Autodesk Fusion 360 part; units mm, degrees
(part 2 of 3)
sketch "Sketch4" plane through (0, 0, 0) normal (0, 0, 1) x (-1, 0, 0)
  line L0 (0, -15.875) -> (0, -11.049)
  line L1 (0, -11.049) -> (-10.16, -11.049)
  line L2 (-10.16, -11.049) -> (-10.16, -15.875)
  line L3 (-10.16, -15.875) -> (0, -15.875)
sketch "Sketch5" plane through (10.16, 0, 0) normal (1, 0, 0) x (0, -1, 0)
  line L0 (-11.049, 0.762) -> (-0.762, 11.049)
  line L1 (-0.762, 11.049) -> (0.762, 11.049)
  line L2 (0.762, 11.049) -> (11.049, 0.762)
  line L3 (11.049, 0.762) -> (11.049, 0)
  line L4 (11.049, 0) -> (15.875, 0)
  line L5 (15.875, 0) -> (15.875, 12.7)
  line L6 (15.875, 12.7) -> (-15.875, 12.7)
  line L7 (-15.875, 12.7) -> (-15.875, 0)
  line L8 (-15.875, 0) -> (-11.049, 0)
  line L9 (-11.049, 0) -> (-11.049, 0.762)
  arc A0 (-12.7, 0) -> (12.7, 0) centre (0, 0) ccw
  line L10 (-11.6397, -5.08) -> (15.875, -5.08)
  line L11 (11.6397, -5.08) -> (-15.875, -5.08)
  line L12 (-15.875, 0) -> (-11.049, 0)
  dimension "d21" = 5.08
  dimension "d22" = 5.08
  dimension "d34" = 12.7
  constraint coincident A0.centre origin
  constraint coincident L8 A0.end
  constraint coincident L4 A0.start
  constraint coincident A0 L10.start
  constraint coincident L5 L10.end
  constraint perpendicular L5 L10
  constraint coincident A0 L11.start
  constraint coincident L7 L11.end
  constraint perpendicular L7 L11
  measures "d21" distance of L4 L10
  measures "d22" distance of L11 L12
  measures "d34" radius of A0
extrude "Extrude3" add sketch "Sketch5" against normal up to surface (10.16 mm away) contours L0 L1 L2 L3 L4 L5 L6 L7 L8 L9 L12
sketch "Sketch7" plane through (0, 0, 0) normal (0, 0, 1) x (-1, 0, 0)
  line L0 (0, 11.049) -> (0, 15.875)
  line L1 (0, 15.875) -> (-10.16, 15.875)
  line L2 (-10.16, 15.875) -> (-10.16, 11.049)
  line L3 (-10.16, 11.049) -> (0, 11.049)
  circle A0 centre (-5.08, 13.589) radius 1.6
  circle A1 centre (-5.08, -13.589) radius 1.6
  line L4 (-10.16, -15.875) -> (0, -15.875)
  line L5 (-10.16, -11.049) -> (-10.16, -15.875)
  dimension "d35" = 3.2
  dimension "d36" = 3.2
  dimension "d37" = 2.286
  dimension "d38" = 2.286
  dimension "d39" = 5.08
  dimension "d40" = 5.08
  measures "d35" diameter of A1
  measures "d36" diameter of A0
  measures "d37" distance of A1.centre L4
  measures "d38" distance of L1 A0.centre
  measures "d39" distance of L2 A0.centre
  measures "d40" distance of A1.centre L5
extrude "Extrude5" cut sketch "Sketch7" against normal blind 12.7 contours A0 | A1
sketch "Sketch8" plane through (0, 0, 0) normal (-1, 0, 0) x (0, -1, 0)
  line L0 (-0.762, -11.049) -> (-11.049, -0.762)
  line L1 (-11.049, -0.762) -> (-11.049, 0)
  line L2 (-11.049, 0) -> (-15.875, 0)
  line L3 (-15.875, 0) -> (-15.875, -12.7)
  line L4 (-15.875, -12.7) -> (15.875, -12.7)
  line L5 (15.875, -12.7) -> (15.875, 0)
  line L6 (15.875, 0) -> (11.049, 0)
  line L7 (11.049, 0) -> (11.049, -0.762)
  line L8 (11.049, -0.762) -> (0.762, -11.049)
  line L9 (0.762, -11.049) -> (-0.762, -11.049)
  arc A0 (-12.7, 0) -> (12.7, 0) centre (0, 0) ccw
  line L10 (-11.6397, -5.08) -> (-15.875, -5.08)
  line L11 (11.6397, -5.08) -> (15.875, -5.08)
  line L12 (-15.875, 0) -> (-11.049, 0)
  dimension "d43" = 5.08
  dimension "d44" = 5.08
  constraint coincident A0.centre origin
  constraint tangent L4 A0
  constraint coincident L6 A0.end
  constraint coincident L2 A0.start
  constraint coincident A0 L10.start
  constraint coincident L3 L10.end
  constraint perpendicular L3 L10
  constraint coincident A0 L11.start
  constraint coincident L5 L11.end
  constraint perpendicular L5 L11
  measures "d43" distance of L10 L12
  measures "d44" distance of L6 L11
extrude "Extrude6" cut sketch "Sketch8" against normal blind 10.16 contours L3 L4 A0 L10 | L4 L5 A0 L11

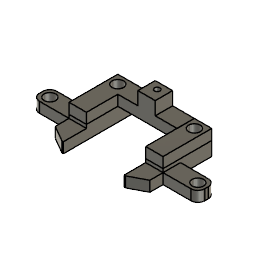
design "Static Arm"
Autodesk Fusion 360 part; units mm, degrees
sketch "Sketch1" plane through (0, 0, 0) normal (0, 0, 1) x (1, 0, 0)
  line L0 (2.54, 0) -> (57.7596, 0)
  line L1 (60.2996, 2.54) -> (60.2996, 3.81)
  line L2 (57.7596, 6.35) -> (2.54, 6.35)
  line L3 (0, 3.81) -> (0, 2.54)
  circle A0 centre (3.175, 3.175) radius 2.0955
  circle A1 centre (57.1246, 3.175) radius 2.0955
  arc A2 (60.2996, 3.81) -> (57.7596, 6.35) centre (57.7596, 3.81) ccw
  arc A3 (57.7596, 0) -> (60.2996, 2.54) centre (57.7596, 2.54) ccw
  arc A4 (2.54, 6.35) -> (0, 3.81) centre (2.54, 3.81) ccw
  arc A5 (0, 2.54) -> (2.54, 0) centre (2.54, 2.54) ccw
  line L4 (13.335, 17.78) -> (41.275, 17.78)
  line L5 (41.275, 17.78) -> (41.275, 11.43)
  line L6 (41.275, 11.43) -> (13.335, 11.43)
  line L7 (13.335, 11.43) -> (13.335, 17.78)
  line L8 (13.335, 17.78) -> (19.685, 17.78)
  line L9 (19.685, 17.78) -> (19.685, 0)
  line L10 (19.685, 0) -> (13.335, 0)
  line L11 (13.335, 0) -> (13.335, 17.78)
  line L12 (47.5996, 17.78) -> (41.2496, 17.78)
  line L13 (41.2496, 17.78) -> (41.2496, 0)
  line L14 (41.2496, 0) -> (47.5996, 0)
  line L15 (47.5996, 0) -> (47.5996, 17.78)
  point P0 (60.2996, 0)
  dimension "d1" = 6.35
  dimension "d2" = 60.2996
  dimension "d3" = 4.191
  dimension "d4" = 4.191
  dimension "d5" = 53.9496
  dimension "d6" = 3.175
  dimension "d7" = 3.175
  dimension "d8" = 2.54
  dimension "d9" = 2.54
  dimension "d10" = 2.54
  dimension "d11" = 2.54
  dimension "d14" = 6.35
  dimension "d15" = 10.16
  dimension "d17" = 6.35
  dimension "d18" = 10.16
  dimension "d19" = 5.08
  dimension "d20" = 6.35
  dimension "d39" = 27.94
  constraint horizontal L0
  constraint vertical L1
  constraint horizontal L2
  constraint vertical L3
  constraint horizontal A0.centre A1.centre
  constraint tangent L2 A2
  constraint tangent L1 A2
  constraint coincident P0 L0
  constraint coincident P0 L1
  constraint tangent L0 A3
  constraint tangent L1 A3
  constraint tangent L3 A4
  constraint tangent L2 A4
  constraint coincident origin L3
  constraint coincident origin L0
  constraint tangent L3 A5
  constraint tangent L0 A5
  constraint horizontal L4
  constraint vertical L5
  constraint horizontal L6
  constraint vertical L7
  constraint horizontal L8
  constraint vertical L9
  constraint horizontal L10
  constraint vertical L11
  constraint coincident L0 L9.end
  constraint horizontal L12
  constraint vertical L13
  constraint horizontal L14
  constraint vertical L15
  constraint coincident L0 L13.end
  constraint coincident L4 L12.start
  measures "d1" distance of L0 L2
  measures "d2" distance of origin P0
  measures "d3" diameter of A0
  measures "d4" diameter of A1
  measures "d5" distance of A0.centre A1.centre
  measures "d6" distance of L3 A0.centre
  measures "d7" vertical distance of origin A0.centre
  measures "d8" radius of A2
  measures "d9" radius of A3
  measures "d10" radius of A4
  measures "d11" radius of A5
  measures "d14" distance of L4 L6
  measures "d15" distance of A0.centre L11
  measures "d17" distance of L13 L15
  measures "d18" distance of A3.centre L15
  measures "d19" distance of L2 L6
  measures "d20" distance of L9 L11
  measures "d39" distance of L4.start L4.end
extrude "Extrude1" add sketch "Sketch1" along normal blind 3.81 contours L0 L2 L3 A4 A5 L11 | L0 L2 L9 L10 L11 | L2 L6 L9 L11 | L0 L2 L13 L14 L15 | L4 L6 L7 L8 L9 L11 | L0 L1 L2 A2 A3 L15 | L2 L5 L6 L12 L13 L15 | L4 L6 L9 L13 makes body 1
sketch "Sketch5" plane through (0, 0, 3.81) normal (0, 0, -1) x (1, 0, 0)
  circle A0 centre (63.4746, -3.175) radius 2.0955
  circle A1 centre (3.175, -3.175) radius 2.0955
  line L0 (47.5996, 0) -> (47.5996, -11.43)
  line L1 (47.5996, -11.43) -> (19.335, -11.43)
  line L2 (19.335, -11.43) -> (19.335, 0)
  line L3 (19.335, 0) -> (2.54, 0)
  arc A2 (2.54, 0) -> (0, -2.54) centre (2.54, -2.54) ccw
  line L4 (0, -2.54) -> (0, -3.81)
  arc A3 (0, -3.81) -> (2.54, -6.35) centre (2.54, -3.81) ccw
  line L5 (2.54, -6.35) -> (13.335, -6.35)
  line L6 (13.335, -6.35) -> (13.335, -17.78)
  line L7 (13.335, -17.78) -> (53.9496, -17.78)
  line L8 (53.9496, -17.78) -> (53.9496, -6.35)
  line L9 (53.9496, -6.35) -> (64.1096, -6.35)
  arc A4 (64.1096, -6.35) -> (66.6496, -3.81) centre (64.1096, -3.81) ccw
  line L10 (66.6496, -3.81) -> (66.6496, -2.54)
  arc A5 (66.6496, -2.54) -> (64.1096, 0) centre (64.1096, -2.54) ccw
  line L11 (64.1096, 0) -> (47.5996, 0)
  line L12 (26.9748, -11.43) -> (33.3248, -11.43)
  line L13 (33.3248, -11.43) -> (33.3248, -17.78)
  line L14 (33.3248, -17.78) -> (26.9748, -17.78)
  line L15 (26.9748, -17.78) -> (26.9748, -11.43)
  circle A6 centre (3.175, -3.175) radius 2.0955
  line L16 (13.335, -17.78) -> (13.335, -6.35)
  line L17 (13.335, -6.35) -> (2.54, -6.35)
  arc A7 (0, -3.81) -> (2.54, -6.35) centre (2.54, -3.81) ccw
  line L18 (0, -3.81) -> (0, -2.54)
  arc A8 (2.54, 0) -> (0, -2.54) centre (2.54, -2.54) ccw
  line L19 (2.54, 0) -> (19.685, 0)
  line L20 (19.685, 0) -> (19.685, -11.43)
  line L21 (19.685, -11.43) -> (41.2496, -11.43)
  line L22 (41.2496, -11.43) -> (41.2496, -17.78)
  line L23 (41.2496, -17.78) -> (13.335, -17.78)
  dimension "d35" = 6.35
  dimension "d36" = 26.9748
  constraint horizontal L12
  constraint vertical L13
  constraint horizontal L14
  constraint vertical L15
  constraint coincident L7 L13.end
  constraint coincident L1 L12.start
  measures "d35" distance of L13 L15
  measures "d36" distance of origin L15
extrude "Extrude4" add sketch "Sketch5" against normal blind 4.8006 contours L1 L7 L12 L13 L14 L15 L21 L23 bodies 1
sketch "Sketch2" plane through (0, 0, 8.6106) normal (0, 0, -1) x (1, 0, 0)
  circle A0 centre (63.4746, -3.175) radius 2.0955
  circle A1 centre (3.175, -3.175) radius 2.0955
  line L0 (47.5996, 0) -> (47.5996, -11.43)
  line L1 (47.5996, -11.43) -> (36.4998, -11.43)
  line L2 (19.335, -11.43) -> (19.335, 0)
  line L3 (19.335, 0) -> (2.54, 0)
  arc A2 (2.54, 0) -> (0, -2.54) centre (2.54, -2.54) ccw
  line L4 (0, -2.54) -> (0, -3.81)
  arc A3 (0, -3.81) -> (2.54, -6.35) centre (2.54, -3.81) ccw
  line L5 (2.54, -6.35) -> (13.335, -6.35)
  line L6 (13.335, -6.35) -> (13.335, -17.78)
  line L7 (36.4998, -17.78) -> (53.9496, -17.78)
  line L8 (53.9496, -17.78) -> (53.9496, -6.35)
  line L9 (53.9496, -6.35) -> (64.1096, -6.35)
  arc A4 (64.1096, -6.35) -> (66.6496, -3.81) centre (64.1096, -3.81) ccw
  line L10 (66.6496, -3.81) -> (66.6496, -2.54)
  arc A5 (66.6496, -2.54) -> (64.1096, 0) centre (64.1096, -2.54) ccw
  line L11 (64.1096, 0) -> (47.5996, 0)
  circle A6 centre (30.1498, -15.3416) radius 1
  line L12 (36.4998, -11.43) -> (36.4998, -17.78)
  line L13 (30.1498, -17.78) -> (30.1498, -11.43)
  line L14 (30.1498, -11.43) -> (19.335, -11.43)
  line L15 (13.335, -17.78) -> (30.1498, -17.78)
  line L16 (30.1498, -17.78) -> (36.4998, -17.78)
  line L17 (36.4998, -17.78) -> (36.4998, -11.43)
  line L18 (36.4998, -11.43) -> (30.1498, -11.43)
  line L19 (30.1498, -11.43) -> (30.1498, -17.78)
  circle A7 centre (63.4746, -3.175) radius 2.0955
  circle A8 centre (3.175, -3.175) radius 2.0955
  line L20 (47.5996, -11.43) -> (47.5996, 0)
  line L21 (2.54, 0) -> (19.335, 0)
  arc A9 (66.6496, -2.54) -> (64.1096, 0) centre (64.1096, -2.54) ccw
  line L22 (66.6496, -2.54) -> (66.6496, -3.81)
  arc A10 (64.1096, -6.35) -> (66.6496, -3.81) centre (64.1096, -3.81) ccw
  line L23 (13.335, -6.35) -> (2.54, -6.35)
  line L24 (53.9496, -6.35) -> (53.9496, -17.78)
  line L25 (30.1498, -17.78) -> (13.335, -17.78)
  line L26 (13.335, -17.78) -> (13.335, -6.35)
  arc A11 (0, -3.81) -> (2.54, -6.35) centre (2.54, -3.81) ccw
  line L27 (0, -3.81) -> (0, -2.54)
  arc A12 (2.54, 0) -> (0, -2.54) centre (2.54, -2.54) ccw
  line L28 (19.335, 0) -> (19.335, -11.43)
  line L29 (19.335, -11.43) -> (30.1498, -11.43)
  line L30 (30.1498, -11.43) -> (30.1498, -17.78)
  line L31 (36.4998, -17.78) -> (36.4998, -11.43)
  line L32 (36.4998, -11.43) -> (47.5996, -11.43)
  line L33 (47.5996, 0) -> (64.1096, 0)
  line L34 (64.1096, -6.35) -> (53.9496, -6.35)
  line L35 (53.9496, -17.78) -> (36.4998, -17.78)
  line L36 (33.3248, -17.78) -> (26.9748, -17.78)
  line L37 (26.9748, -17.78) -> (26.9748, -11.43)
  line L38 (26.9748, -11.43) -> (33.3248, -11.43)
  line L39 (33.3248, -11.43) -> (33.3248, -17.78)
  dimension "d21" = 2
  dimension "d24" = 3.9116
  dimension "d53" = 30.1498
  measures "d21" diameter of A6
  measures "d24" distance of L1 A6.centre
  measures "d53" distance of L4 A6.centre
extrude "Extrude2" cut sketch "Sketch2" along normal blind 12.7 contours A6 L13 L19 L30 | A6 L13 L19 L30 bodies 1
sketch "Sketch3" plane through (0, 0, 3.81) normal (0, 0, 1) x (-1, 0, 0)
  line L0 (-41.2496, 0) -> (-57.7596, 0)
  line L1 (-57.7596, -6.35) -> (-47.5996, -6.35)
  line L2 (-41.275, -11.43) -> (-41.2496, -11.43)
  circle A0 centre (-16.51, -14.605) radius 2.1
  circle A1 centre (-44.4246, -14.605) radius 2.1
  line L3 (-47.5996, -6.35) -> (-47.5996, -17.78)
  line L4 (-47.5996, -17.78) -> (-41.275, -17.78)
  line L5 (-41.275, -17.78) -> (-41.275, -11.43)
  line L6 (-41.2496, -11.43) -> (-41.2496, 0)
  arc A2 (-57.7596, 0) -> (-60.2996, -2.54) centre (-57.7596, -2.54) ccw
  line L7 (-60.2996, -2.54) -> (-60.2996, -3.81)
  arc A3 (-60.2996, -3.81) -> (-57.7596, -6.35) centre (-57.7596, -3.81) ccw
  circle A4 centre (-57.1246, -3.175) radius 2.0955
  dimension "d27" = 4.2
  dimension "d28" = 4.2
  dimension "d40" = 14.605
  dimension "d41" = 16.51
  dimension "d42" = 27.9146
  constraint horizontal A0.centre A1.centre
  measures "d27" diameter of A1
  measures "d28" diameter of A0
  measures "d40" vertical distance of origin A0.centre
  measures "d41" horizontal distance of origin A0.centre
  measures "d42" distance of A0.centre A1.centre
extrude "Extrude3" cut sketch "Sketch3" against normal blind 3.81 contours A0 | A1 bodies 1
sketch "Sketch6" plane through (0, 0, 0) normal (0, 0, -1) x (1, 0, 0)
  circle A0 centre (44.4246, -14.605) radius 2.1
  circle A1 centre (57.1246, -3.175) radius 2.0955
  line L0 (47.5996, -6.35) -> (57.7596, -6.35)
  arc A2 (57.7596, -6.35) -> (60.2996, -3.81) centre (57.7596, -3.81) ccw
  line L1 (60.2996, -3.81) -> (60.2996, -2.54)
  arc A3 (60.2996, -2.54) -> (57.7596, 0) centre (57.7596, -2.54) ccw
  line L2 (57.7596, 0) -> (41.2496, 0)
  line L3 (41.2496, 0) -> (41.2496, -11.43)
  line L4 (41.2496, -11.43) -> (41.275, -11.43)
  line L5 (41.275, -11.43) -> (41.275, -17.78)
  line L6 (41.275, -17.78) -> (47.5996, -17.78)
  line L7 (47.5996, -17.78) -> (47.5996, -6.35)
  line L8 (41.2496, 0) -> (47.5996, 0)
  line L9 (47.5996, 0) -> (47.5996, -17.78)
  line L10 (47.5996, -17.78) -> (41.2496, -17.78)
  line L11 (41.2496, -17.78) -> (41.2496, 0)
  line L12 (47.5996, 0) -> (57.7596, 0)
  line L13 (60.2996, -2.54) -> (60.2996, -3.81)
  line L14 (57.7596, -6.35) -> (47.5996, -6.35)
  line L15 (47.5996, -6.35) -> (47.5996, 0)
  arc A4 (60.2996, -2.54) -> (57.7596, 0) centre (57.7596, -2.54) ccw
  arc A5 (57.7596, -6.35) -> (60.2996, -3.81) centre (57.7596, -3.81) ccw
  line L16 (19.685, -17.78) -> (13.335, -17.78)
  line L17 (13.335, -17.78) -> (13.335, 0)
  line L18 (13.335, 0) -> (19.685, 0)
  line L19 (19.685, 0) -> (19.685, -17.78)
  line L20 (13.335, 0) -> (2.54, 0)
  line L21 (0, -2.54) -> (0, -3.81)
  line L22 (2.54, -6.35) -> (13.335, -6.35)
  line L23 (13.335, -6.35) -> (13.335, 0)
  arc A6 (2.54, 0) -> (0, -2.54) centre (2.54, -2.54) ccw
  arc A7 (0, -3.81) -> (2.54, -6.35) centre (2.54, -3.81) ccw
  circle A8 centre (3.175, -3.175) radius 2.0955
  circle A9 centre (16.51, -14.5999) radius 2.0955
  point P0 (19.685, 0)
  point P1 (13.335, -17.78)
  point P2 (0, -2.54)
  dimension "d43" = 2.54
  dimension "d44" = 2.54
  dimension "d45" = 10.16
  dimension "d46" = 1.27
  dimension "d54" = 6.35
  dimension "d55" = 2.54
  dimension "d56" = 2.54
  dimension "d57" = 6.35
  dimension "d58" = 3.175
  dimension "d59" = 4.191
  dimension "d60" = 3.175
  dimension "d61" = 4.191
  dimension "d62" = 3.1801
  dimension "d63" = 3.175
  constraint horizontal L8
  constraint vertical L9
  constraint horizontal L10
  constraint vertical L11
  constraint coincident L6.end L7.start
  constraint coincident L2.end L3.start
  constraint horizontal L12
  constraint vertical L13
  constraint horizontal L14
  constraint vertical L15
  constraint tangent L12 A4
  constraint tangent L13 A4
  constraint tangent L13 A5
  constraint tangent L14 A5
  constraint horizontal L16
  constraint vertical L17
  constraint horizontal L18
  constraint vertical L19
  constraint coincident P0 L18.end
  constraint coincident P1 L16.end
  constraint horizontal L20
  constraint vertical L21
  constraint horizontal L22
  constraint vertical L23
  constraint tangent L21 A6
  constraint tangent L20 A6
  constraint tangent L21 A7
  constraint tangent L22 A7
  constraint coincident P2 L21.start
  measures "d43" radius of A4
  measures "d44" radius of A5
  measures "d45" distance of L0.start L0.end
  measures "d46" distance of L1.end A2.end
  measures "d54" distance of L17 L19
  measures "d55" radius of A6
  measures "d56" radius of A7
  measures "d57" distance of L20 L22
  measures "d58" distance of L20 A8.centre
  measures "d59" diameter of A8
  measures "d60" distance of L21 A8.centre
  measures "d61" diameter of A9
  measures "d62" distance of L16 A9.centre
  measures "d63" distance of L17 A9.centre
extrude "Extrude6" cut sketch "Sketch6" against normal blind 7.62 contours L0 A2 L1 A3 L2 L9 L12 L13 L14 L15 A4 A5 | L17 L20 L21 L22 L23 A6 A7 bodies 1
extrude "Extrude5" add sketch "Sketch6" along normal blind 5.08 separate body contours L0 A2 L1 A3 L2 L9 L12 L13 L14 L15 A4 A5 | L2 L3 L4 L5 L6 L7 L8 L9 L10 L11 L15 | L16 L17 L18 L19 L23 | L17 L20 L21 L22 L23 A6 A7 makes body 2 at (43.3747, 5.9267, 0) makes body 3 at (12.6943, 2.8719, 0)
extrude "Extrude7" cut sketch "Sketch6" along normal blind 1.27 contours L0 A2 L1 A3 L2 L9 L12 L13 L14 L15 A4 A5 | L17 L20 L21 L22 L23 A6 A7 bodies 2
extrude "Extrude8" cut sketch "Sketch6" along normal blind 1.27 contours L17 L20 L21 L22 L23 A6 A7 bodies 3
sketch "Sketch7" plane through (0, 0, 0) normal (0, -1, 0) x (1, 0, 0)
  line L0 (13.335, -1.27) -> (2.54, -1.27)
  line L1 (2.54, -1.27) -> (2.54, -5.08)
  line L2 (2.54, -5.08) -> (19.685, -5.08)
  line L3 (19.685, -5.08) -> (19.685, 0)
  line L4 (19.685, 0) -> (13.335, 0)
  line L5 (13.335, 0) -> (13.335, -1.27)
  line L6 (13.335, -1.27) -> (19.685, -1.27)
  line L7 (19.685, -1.27) -> (19.685, -5.08)
  line L8 (19.685, -5.08) -> (13.335, -5.08)
  line L9 (13.335, -5.08) -> (13.335, -1.27)
  dimension "d66" = 6.35
  constraint horizontal L6
  constraint vertical L7
  constraint horizontal L8
  constraint vertical L9
  constraint coincident L2 L3.start
  constraint coincident L0 L5.end
  constraint coincident L2.end L3.start
  measures "d66" distance of L7 L9
extrude "Extrude9" add sketch "Sketch7" along normal blind 8.4226 contours L2 L3 L6 L7 L8 L9 bodies 3
chamfer "Chamfer1" distance 5.842 angle 30.099 1 edges at (13.335, -8.4226, -3.175) measured on face at (15.4517, -8.4226, -3.81) on bodies 3
sketch "Sketch8" plane through (0, 0, 0) normal (0, -1, 0) x (1, 0, 0)
  line L0 (57.7596, -1.27) -> (47.5996, -1.27)
  line L1 (47.5996, -1.27) -> (47.5996, 0)
  line L2 (47.5996, 0) -> (41.2496, 0)
  line L3 (41.2496, 0) -> (41.2496, -5.08)
  line L4 (41.2496, -5.08) -> (57.7596, -5.08)
  line L5 (57.7596, -5.08) -> (57.7596, -1.27)
  line L6 (41.2496, -5.08) -> (47.5996, -5.08)
  line L7 (47.5996, -5.08) -> (47.5996, -1.27)
  line L8 (47.5996, -1.27) -> (41.2496, -1.27)
  line L9 (41.2496, -1.27) -> (41.2496, -5.08)
  constraint horizontal L6
  constraint vertical L7
  constraint horizontal L8
  constraint vertical L9
  constraint coincident L0.end L1.start
  constraint coincident L3.end L4.start
extrude "Extrude10" add sketch "Sketch8" along normal blind 7.874 contours L3 L4 L6 L7 L8 L9 bodies 2
chamfer "Chamfer2" distance 5.842 angle 27.549 1 edges at (47.5996, -7.874, -3.175) measured on face at (45.4829, -7.874, -3.81) on bodies 2
equation "d5 = 2.374 in - 0.25 in"
equation "d36 = ( 2.624 / 2 ) * 1 in - 0.25 in"
equation "d42 = 1.349 in - 0.25 in"
equation "d53 = ( 2.374 / 2 ) * 1 in"

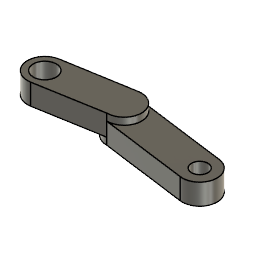
design "Right Control Arm"
Autodesk Fusion 360 part; units mm, degrees
sketch "Sketch1" plane through (0, 0, 0) normal (0, 0, 1) x (1, 0, 0)
  circle A0 centre (0, 0) radius 2.0955
  circle A1 centre (28.2448, 0) radius 1.5
  circle A2 centre (0, 0) radius 3.175
  circle A3 centre (28.2448, 0) radius 3.175
  circle A4 centre (12.3698, 2.0955) radius 3.175
  line L0 (27.8238, -3.147) -> (12.3698, -1.0795)
  line L1 (0.5419, -3.1284) -> (12.3698, -1.0795)
  line L2 (28.6603, 3.1477) -> (12.7853, 5.2432)
  line L3 (-0.5303, 3.1304) -> (11.8395, 5.2259)
  dimension "d1" = 3
  dimension "d2" = 4.191
  dimension "d3" = 28.2448
  dimension "d4" = 6.35
  dimension "d5" = 6.35
  dimension "d12" = 6.35
  dimension "d22" = 15.875
  dimension "d23" = 2.0955
  constraint coincident A0.centre A2.centre
  constraint concentric A1 A3
  constraint horizontal A0.centre A1.centre
  constraint coincident A3 L0.start
  constraint coincident A4 L0.end
  constraint coincident A2 L1.start
  constraint coincident A3 L2.start
  constraint coincident A4 L2.end
  constraint tangent A4 L2
  constraint coincident A2 L3.start
  constraint coincident A4 L3.end
  constraint tangent A4 L3
  constraint tangent A3 L2
  constraint tangent A3 L0
  constraint tangent A2 L1
  constraint tangent A2 L3
  constraint vertical A4.centre L0.end
  measures "d1" diameter of A1
  measures "d2" diameter of A0
  measures "d3" distance of A0.centre A1.centre
  measures "d4" diameter of A3
  measures "d5" diameter of A2
  measures "d12" diameter of A4
  measures "d22" horizontal distance of A1.centre A4.centre
  measures "d23" vertical distance of A1.centre A4.centre
extrude "Extrude1" add sketch "Sketch1" along normal blind 3.81 contours A4 | A3 A4 L0 L2 | A3
extrude "Extrude4" add sketch "Sketch1" along normal blind 5.08 contours A4
extrude "Extrude3" add sketch "Sketch1" along normal blind 5.08 and the other way blind -1.27 contours A2 | A2 A4 L1 L3 | A4
sketch "Sketch2" plane through (0, 0, 0) normal (0, 0, -1) x (1, 0, 0)
  circle A0 centre (28.2448, 0) radius 1.5
  line L0 (16.8148, -3.175) -> (28.2448, -3.175)
  arc A1 (28.2448, -3.175) -> (28.2448, 3.175) centre (28.2448, 0) ccw
  line L1 (28.2448, 3.175) -> (16.8148, 3.175)
  circle A2 centre (0, 0) radius 2.0955
  circle A3 centre (0, 0) radius 3.175
  arc A4 (16.8148, 3.175) -> (16.8148, -3.175) centre (16.8148, 0) ccw
  dimension "d8" = 4.191
  dimension "d9" = 6.35
  measures "d8" diameter of A2
  measures "d9" diameter of A3
extrude "Extrude2" [rolled back] along distance 3.81 taper angle 0
equation "d3 = 1.235 in - 0.123 in"
equation "d23 = ( 0.165 / 2 ) * 1 in"

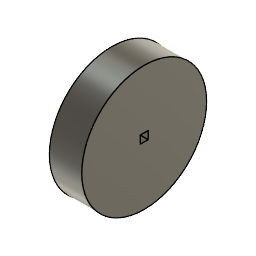
design "Wheel"
Autodesk Fusion 360 part; units mm, degrees
sketch "Sketch1" plane through (0, 0, 0) normal (1, 0, 0) x (0, 1, 0)
  circle A0 centre (0, 0) radius 25.4
  line L0 (1.6002, 1.6002) -> (-1.6002, 1.6002)
  line L1 (-1.6002, 1.6002) -> (-1.6002, -1.6002)
  line L2 (-1.6002, -1.6002) -> (1.6002, -1.6002)
  line L3 (1.6002, -1.6002) -> (1.6002, 1.6002)
  line L4 (1.6002, 1.6002) -> (-1.6002, -1.6002) construction
  line L5 (-1.6002, 1.6002) -> (1.6002, -1.6002) construction
  dimension "d1" = 50.8
  dimension "d2" = 3.2004
  dimension "d3" = 3.2004
  constraint coincident A0.centre origin
  constraint horizontal L0
  constraint perpendicular L0 L1
  constraint parallel L0 L2
  constraint parallel L1 L3
  constraint coincident L4 A0.centre
  constraint coincident L5 A0.centre
  measures "d1" diameter of A0
  measures "d2" distance of L0.end L1.end
  measures "d3" distance of L1.end L2.end
extrude "Extrude1" add sketch "Sketch1" along normal blind 13.208

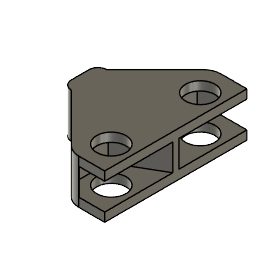
design "Wheel mount"
Autodesk Fusion 360 part; units mm, degrees
sketch "Sketch1" plane through (0, 0, 0) normal (0, 0, 1) x (1, 0, 0)
  line L0 (1.27, -2.54) -> (8.89, -2.54)
  line L1 (8.89, -2.54) -> (8.89, 2.54)
  line L2 (8.89, 2.54) -> (1.27, 2.54)
  line L3 (0, 1.27) -> (0, -1.27)
  line L4 (16.51, 10.16) -> (16.51, -10.16)
  line L5 (8.89, -10.16) -> (8.89, 10.16)
  arc A0 (1.27, 2.54) -> (0, 1.27) centre (1.27, 1.27) ccw
  arc A1 (0, -1.27) -> (1.27, -2.54) centre (1.27, -1.27) ccw
  circle A2 centre (10.795, 6.35) radius 2.0955
  circle A3 centre (10.795, -6.35) radius 2.0955
  line L6 (9.9421, 10.16) -> (16.51, 10.16)
  line L7 (9.9421, -10.16) -> (16.51, -10.16)
  line L8 (1.27, -2.54) -> (8.1461, -9.4161)
  line L9 (1.27, 2.54) -> (8.1461, 9.4161)
  arc A4 (9.9421, 10.16) -> (8.1461, 9.4161) centre (9.9421, 7.62) ccw
  arc A5 (8.1461, -9.4161) -> (9.9421, -10.16) centre (9.9421, -7.62) ccw
  line L10 (13.6525, 10.16) -> (13.6525, -10.16)
  dimension "d1" = 1.27
  dimension "d2" = 1.27
  dimension "d5" = 4.191
  dimension "d6" = 4.191
  dimension "d8" = 20.32
  dimension "d9" = 7.62
  dimension "d10" = 1.905
  dimension "d13" = 2.54
  dimension "d14" = 20.32
  dimension "d15" = 2.54
  dimension "d16" = 2.54
  dimension "d17" = 45
  dimension "d18" = 12.7
  dimension "d19" = 6.35
  dimension "d31" = 2.8575
  constraint horizontal L0
  constraint vertical L1
  constraint horizontal L2
  constraint vertical L3
  constraint vertical L4
  constraint vertical L5
  constraint midpoint L1 L5
  constraint tangent L2 A0
  constraint tangent L3 A0
  constraint tangent L0 A1
  constraint tangent L3 A1
  constraint midpoint origin L3
  constraint perpendicular L4 L6
  constraint coincident L5.end L9
  constraint coincident L5.end L6
  constraint tangent L9 A4
  constraint tangent L6 A4
  constraint coincident L5.start L8
  constraint coincident L5.start L7
  constraint tangent L8 A5
  constraint tangent L7 A5
  constraint vertical A2.centre A3.centre
  constraint coincident L6 L10.start
  constraint coincident L7 L10.end
  constraint perpendicular L7 L10
  measures "d1" radius of A0
  measures "d2" radius of A1
  measures "d5" diameter of A2
  measures "d6" diameter of A3
  measures "d8" distance of L4.start L4.end
  measures "d9" distance of L4 L5
  measures "d10" distance of L5 A3.centre
  measures "d13" distance of L3.start L3.end
  measures "d14" distance of L5.end L5.start
  measures "d15" radius of A4
  measures "d16" radius of A5
  measures "d17" angle of L0 L8
  measures "d18" vertical distance of A2.centre A3.centre
  measures "d19" vertical distance of origin A2.centre
  measures "d31" distance of A3.centre L10
extrude "Extrude1" add sketch "Sketch1" along normal blind 6.35 contours L0 L1 L2 L3 L5 A0 A1 | L0 L5 A3 L8 A5 | L1 L5 A2 A3 L6 L7 A4 A5 L10 | L2 L5 A2 L9 A4
sketch "Sketch3" plane through (13.6525, 0, 0) normal (1, 0, 0) x (0, 1, 0)
  line L0 (-10.16, 0) -> (10.16, 0)
  line L1 (10.16, 0) -> (10.16, 6.35)
  line L2 (10.16, 6.35) -> (-10.16, 6.35)
  line L3 (-10.16, 6.35) -> (-10.16, 0)
  line L4 (3.81, 5.08) -> (8.89, 5.08)
  line L5 (8.89, 5.08) -> (8.89, 1.27)
  line L6 (8.89, 1.27) -> (3.81, 1.27)
  line L7 (3.81, 1.27) -> (3.81, 5.08)
  line L8 (-10.16, 0) -> (10.16, 0)
  line L9 (10.16, 0) -> (10.16, 6.35)
  line L10 (10.16, 6.35) -> (-10.16, 6.35)
  line L11 (-10.16, 6.35) -> (-10.16, 0)
  line L12 (-8.89, 5.08) -> (-3.81, 5.08)
  line L13 (-3.81, 5.08) -> (-3.81, 1.27)
  line L14 (-3.81, 1.27) -> (-8.89, 1.27)
  line L15 (-8.89, 1.27) -> (-8.89, 5.08)
  dimension "d25" = 3.81
  dimension "d26" = 5.08
  dimension "d27" = 1.27
  dimension "d28" = 1.27
  dimension "d32" = 5.08
  dimension "d33" = 1.27
  dimension "d34" = 1.27
  dimension "d35" = 3.81
  constraint horizontal L4
  constraint vertical L5
  constraint horizontal L6
  constraint vertical L7
  constraint horizontal L12
  constraint vertical L13
  constraint horizontal L14
  constraint vertical L15
  measures "d25" distance of L4.end L5.end
  measures "d26" distance of L4.start L4.end
  measures "d27" distance of L1 L5
  measures "d28" distance of L0 L6
  measures "d32" distance of L12.start L12.end
  measures "d33" distance of L3 L15
  measures "d34" distance of L0 L14
  measures "d35" distance of L12.end L13.end
extrude "Extrude3" cut sketch "Sketch3" against normal blind 5.842 contours L4 L5 L6 L7 | L12 L13 L14 L15
sketch "Sketch2" plane through (0, 0, 0) normal (-1, 0, 0) x (0, -1, 0)
  line L0 (-1.27, 0) -> (1.27, 0)
  line L1 (1.27, 0) -> (1.27, 6.35)
  line L2 (1.27, 6.35) -> (-1.27, 6.35)
  line L3 (-1.27, 6.35) -> (-1.27, 0)
  line L4 (1.6002, 4.7752) -> (-1.6002, 4.7752)
  line L5 (-1.6002, 4.7752) -> (-1.6002, 1.5748)
  line L6 (-1.6002, 1.5748) -> (1.6002, 1.5748)
  line L7 (1.6002, 1.5748) -> (1.6002, 4.7752)
  line L8 (1.6002, 4.7752) -> (-1.6002, 1.5748) construction
  line L9 (-1.6002, 4.7752) -> (1.6002, 1.5748) construction
  point P0 (0, 3.175)
  dimension "d20" = 3.2004
  dimension "d21" = 3.2004
  dimension "d22" = 3.175
  constraint horizontal L4
  constraint perpendicular L4 L5
  constraint parallel L4 L6
  constraint parallel L5 L7
  constraint coincident L8 P0
  constraint coincident L9 P0
  constraint vertical origin P0
  measures "d20" distance of L4.end L5.end
  measures "d21" distance of L5.end L6.end
  measures "d22" vertical distance of origin P0
extrude "Extrude2" cut sketch "Sketch2" against normal blind 6.35 contours L3 L4 L5 L6 | L1 L3 L4 L6 | L1 L4 L6 L7
draft "Draft1" angle 30 neutral plane through (7.8105, 0, 0) pull (1, 0, 0) 1 faces at (11.7052, -8.89, 2.54)
draft "Draft2" angle 30 neutral plane through (7.8105, 0, 0) pull (1, 0, 0) 1 faces at (11.7052, -3.81, 3.81)
draft "Draft3" angle 30 neutral plane through (7.8105, 0, 0) pull (1, 0, 0) 1 faces at (11.7052, 3.81, 2.54)
draft "Draft4" angle 30 neutral plane through (7.8105, 0, 0) pull (1, 0, 0) 1 faces at (9.7578, 8.89, 3.81)
equation "d10 = 0.125 in - 0.05 in"
equation "d31 = 0.165 * 0.5 in + 0.03 in"

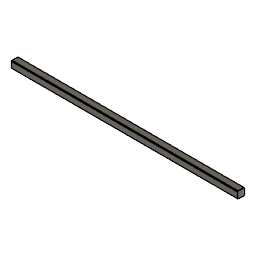
design "Square Shaft"
Autodesk Fusion 360 part; units mm, degrees
sketch "Sketch1" plane through (0, 0, 0) normal (1, 0, 0) x (0, 1, 0)
  line L0 (0, 3.175) -> (3.175, 3.175)
  line L1 (3.175, 3.175) -> (3.175, 0)
  line L2 (3.175, 0) -> (0, 0)
  line L3 (0, 0) -> (0, 3.175)
  dimension "d1" = 3.175
  dimension "d2" = 3.175
  constraint horizontal L0
  constraint vertical L1
  constraint horizontal L2
  constraint vertical L3
  constraint coincident L2.end L3.start
  measures "d1" distance of L0.end L1.end
  measures "d2" distance of L0.start L0.end
extrude "Extrude1" add sketch "Sketch1" along normal blind 101.6
fillet "Fillet1" radius 0.254 4 edges at (50.8, 0, 3.175) (50.8, 3.175, 3.175) (50.8, 0, 0) (50.8, 3.175, 0)

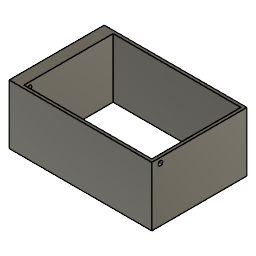
design "Dumping Container"
Autodesk Fusion 360 part; units mm, degrees
sketch "Sketch1" plane through (0, 0, 0) normal (0, 0, 1) x (1, 0, 0)
  line L0 (0, 101.6) -> (12.7, 101.6)
  line L1 (12.7, 101.6) -> (12.7, 0)
  line L2 (12.7, 0) -> (0, 0)
  line L3 (0, 0) -> (0, 101.6)
  line L4 (149.225, 101.6) -> (152.4, 101.6)
  line L5 (152.4, 101.6) -> (152.4, 0)
  line L6 (152.4, 0) -> (149.225, 0)
  line L7 (149.225, 0) -> (149.225, 101.6)
  line L8 (149.225, 98.4098) -> (0, 98.4098)
  line L9 (0, 98.4098) -> (0, 101.6)
  line L10 (0, 101.6) -> (149.225, 101.6)
  line L11 (149.225, 101.6) -> (149.225, 98.4098)
  line L12 (0, 3.175) -> (152.4, 3.175)
  line L13 (152.4, 3.175) -> (152.4, 0)
  line L14 (152.4, 0) -> (0, 0)
  line L15 (0, 0) -> (0, 3.175)
  line L16 (12.7, 3.175) -> (19.05, 3.175)
  line L17 (19.05, 98.4098) -> (12.7, 98.4098)
  line L18 (12.7, 98.4098) -> (12.7, 3.175)
  line L19 (3.1369, 22.3139) -> (9.5631, 22.3139)
  line L20 (9.5631, 22.3139) -> (9.5631, 28.7401)
  line L21 (9.5631, 28.7401) -> (3.1369, 28.7401)
  line L22 (3.1369, 28.7401) -> (3.1369, 22.3139)
  line L23 (3.1369, 72.7837) -> (9.5631, 72.7837)
  line L24 (9.5631, 72.7837) -> (9.5631, 79.2099)
  line L25 (9.5631, 79.2099) -> (3.1369, 79.2099)
  line L26 (3.1369, 79.2099) -> (3.1369, 72.7837)
  dimension "d1" = 101.6
  dimension "d4" = 101.6
  dimension "d5" = 3.175
  dimension "d6" = 3.1902
  dimension "d7" = 12.7
  dimension "d8" = 3.175
  dimension "d9" = 152.4
  dimension "d15" = 6.4262
  dimension "d16" = 6.4262
  dimension "d17" = 6.4262
  dimension "d18" = 6.4262
  dimension "d19" = 3.1369
  dimension "d20" = 3.1369
  dimension "d21" = 50.4698
  dimension "d22" = 22.3901
  constraint horizontal L0
  constraint vertical L1
  constraint horizontal L2
  constraint vertical L3
  constraint horizontal L4
  constraint vertical L5
  constraint horizontal L6
  constraint vertical L7
  constraint horizontal L8
  constraint vertical L9
  constraint horizontal L10
  constraint vertical L11
  constraint coincident L7 L8.start
  constraint horizontal L12
  constraint vertical L13
  constraint horizontal L14
  constraint vertical L15
  constraint coincident L2.end L3.start
  constraint horizontal L16
  constraint horizontal L17
  constraint vertical L18
  constraint coincident L8 L17.start
  constraint coincident L12 L16.start
  constraint coincident L1 L16.start
  constraint horizontal L19
  constraint vertical L20
  constraint horizontal L21
  constraint vertical L22
  constraint horizontal L23
  constraint vertical L24
  constraint horizontal L25
  constraint vertical L26
  measures "d1" distance of L0.start L2.end
  measures "d4" distance of L4.end L5.end
  measures "d5" distance of L12 L14
  measures "d6" distance of L0 L8
  measures "d7" distance of L1 L3
  measures "d8" distance of L5 L7
  measures "d9" distance of L3 L5
  measures "d15" distance of L23.start L23.end
  measures "d16" distance of L23.start L25.end
  measures "d17" distance of L20.end L21.end
  measures "d18" distance of L19.start L21.end
  measures "d19" distance of L3 L22
  measures "d20" distance of L3 L26
  measures "d21" distance of L21.end L25.end
  measures "d22" vertical distance of L0.start L25.end
extrude "Extrude1" add sketch "Sketch1" along normal blind 63.5 contours L0 L1 L3 L8 L9 L10 | L1 L7 L8 L10 L11 L17 | L1 L3 L8 L12 L18 | L4 L5 L7 L11 L12 | L1 L2 L3 L12 L14 L15 | L1 L7 L12 L14 L16 | L5 L6 L7 L12 L13 L14 | L19 L20 L21 L22 | L23 L24 L25 L26
extrude "Extrude2" cut sketch "Sketch1" along normal blind 50.8 contours L19 L20 L21 L22 | L23 L24 L25 L26
sketch "Sketch2" plane through (0, 0, 0) normal (-1, 0, 0) x (0, -1, 0)
  line L0 (-101.6, 0) -> (0, 0)
  line L1 (0, 0) -> (0, 63.5)
  line L2 (0, 63.5) -> (-101.6, 63.5)
  line L3 (-101.6, 63.5) -> (-101.6, 0)
  line L4 (0, 63.5) -> (-9.144, 63.5)
  line L5 (-9.144, 63.5) -> (-9.144, 58.039)
  line L6 (-9.144, 58.039) -> (0, 58.039)
  line L7 (0, 58.039) -> (0, 63.5)
  circle A0 centre (-9.144, 58.039) radius 2.413
  dimension "d26" = 9.144
  dimension "d27" = 5.461
  dimension "d28" = 4.826
  constraint horizontal L4
  constraint vertical L5
  constraint horizontal L6
  constraint vertical L7
  constraint coincident L1.end L2.start
  constraint coincident L5.end L6.start
  measures "d26" distance of L1.end L4.end
  measures "d27" distance of L1.end L6.end
  measures "d28" diameter of A0
extrude "Extrude3" cut sketch "Sketch2" against normal blind 213.36 contours L5 L6 A0 | L5 L6 A0
equation "d22 = 2 in - ( 1.987 / 2 ) * 1 in - 0.125 in"

design "Front Wheel"
Autodesk Fusion 360 part; units mm, degrees
sketch "Sketch1" plane through (0, 0, 0) normal (0, 0, 1) x (1, 0, 0)
  circle A0 centre (0, 0) radius 25.4
  circle A1 centre (0, 0) radius 6.35
  dimension "d1" = 12.7
  dimension "d2" = 50.8
  constraint coincident A0.centre A1.centre
  measures "d1" diameter of A1
  measures "d2" diameter of A0
extrude "Extrude1" add sketch "Sketch1" along normal blind 9.525
equation "d3 = ( 3 / 8 ) * 1 in"

design "Shaft Collar"
Autodesk Fusion 360 part; units mm, degrees
sketch "Sketch1" plane through (0, 0, 0) normal (0, 0, 1) x (1, 0, 0)
  circle A0 centre (0, 0) radius 5.4991
  circle A1 centre (0, 0) radius 2.032
  dimension "d1" = 10.9982
  dimension "d2" = 4.064
  constraint coincident A0.centre A1.centre
  constraint concentric A0 A1
  measures "d1" diameter of A0
  measures "d2" diameter of A1
extrude "Extrude1" add sketch "Sketch1" along normal blind 6.35

design "Front bushing"
Autodesk Fusion 360 part; units mm, degrees
sketch "Sketch1" plane through (0, 0, 0) normal (0, 0, 1) x (1, 0, 0)
  circle A0 centre (0, 0) radius 6.35
  circle A1 centre (0, 0) radius 2.4956
  dimension "d1" = 12.7
  dimension "d2" = 4.9911
  constraint coincident A0.centre A1.centre
  measures "d1" diameter of A0
  measures "d2" diameter of A1
extrude "Extrude1" add sketch "Sketch1" along normal blind 9.525

design "Dumper"
Autodesk Fusion 360 part; units mm, degrees
sketch "Sketch1" plane through (0, 0, 0) normal (1, 0, 0) x (0, 1, 0)
  line L0 (63.5, 12.7) -> (63.5, 63.5)
  line L1 (63.5, 63.5) -> (0, 63.5)
  line L2 (25.4, 12.7) -> (63.5, 12.7)
  arc A0 (0, 63.5) -> (25.4, 12.7) centre (63.5, 63.5) ccw
  line L3 (66.675, 9.525) -> (66.675, 66.675)
  line L4 (66.675, 66.675) -> (-3.0994, 66.675)
  arc A1 (-3.0994, 66.675) -> (24.356, 9.525) centre (63.5, 63.5) ccw
  line L5 (24.356, 9.525) -> (66.675, 9.525)
  line L6 (0, 63.5) -> (0, 66.675)
  line L7 (66.675, 53.975) -> (66.675, 66.675)
  line L8 (57.4278, 66.675) -> (57.15, 63.5)
  line L9 (57.15, 63.5) -> (52.7056, 12.7)
  line L10 (66.675, 53.975) -> (63.5, 50.8)
  line L11 (54.6003, 63.5) -> (50.1559, 12.7)
  line L12 (63.5, 50.8) -> (55.3235, 42.6235)
  line L13 (52.7056, 12.7) -> (52.4278, 9.525)
  line L14 (50.1559, 12.7) -> (49.8781, 9.525)
  dimension "d2" = 63.5
  dimension "d5" = 3.175
  dimension "d6" = 57.15
  dimension "d7" = 69.7744
  dimension "d8" = 66.675
  dimension "d22" = 6.35
  dimension "d23" = 85
  dimension "d26" = 45
  dimension "d27" = 2.54
  constraint vertical L0
  constraint horizontal L1
  constraint coincident L0.end L1.start
  constraint perpendicular L0 L2
  constraint coincident L4 L6.end
  constraint tangent A0 L6
  constraint vertical L7
  constraint coincident L4 L8.start
  constraint coincident L1 L8.end
  constraint coincident L2 L9.end
  constraint parallel L8 L9
  constraint coincident L0 L10.end
  constraint coincident L1 L11.start
  constraint coincident L2 L11.end
  constraint parallel L9 L11
  constraint coincident L9 L12.end
  constraint parallel L10 L12
  constraint coincident L5 L13.end
  constraint parallel L9 L13
  constraint coincident L5 L14.end
  constraint parallel L11 L14
  measures "d2" distance of origin L1.end
  measures "d6" distance of L3.start L3.end
  measures "d7" distance of L3.end L4.end
  measures "d8" horizontal distance of origin L3.start
  measures "d22" distance of L0.end L8.end
  measures "d23" angle of L2 L9
  measures "d26" angle of L3 L10
  measures "d27" distance of L9 L11
extrude "Extrude1" add sketch "Sketch1" along normal blind 136.525 contours L2 L5 L13 L14 | L1 L2 L9 L11 | L2 A0 L4 A1 L5 L6 L14 | L1 L2 A0 L11
extrude "Extrude2" cut sketch "Sketch1" along normal blind 133.9977 and the other way blind -2.54 contours L0 L2 L9 L12 | L1 L2 A0 L11
sketch "Sketch6" plane through (136.525, 0, 0) normal (1, 0, 0) x (0, 1, 0)
  line L0 (52.4278, 9.525) -> (57.15, 63.5)
  line L1 (57.15, 63.5) -> (0, 63.5)
  line L2 (0, 63.5) -> (0, 66.675)
  line L3 (0, 66.675) -> (-3.0994, 66.675)
  arc A0 (-3.0994, 66.675) -> (24.356, 9.525) centre (63.5, 63.5) ccw
  line L4 (24.356, 9.525) -> (52.4278, 9.525)
  line L5 (57.15, 63.5) -> (57.15, 58.039)
  circle A1 centre (57.15, 58.039) radius 5.461
  line L6 (52.4278, 9.525) -> (62.4918, 56.9043)
  dimension "d38" = 5.461
  constraint coincident L0.end L1.start
  constraint perpendicular L1 L5
  constraint coincident L5.end A1.centre
  constraint coincident L0.end A1
  constraint coincident L0.start L4.end
  constraint coincident A1 L6.end
  constraint tangent A1 L6
  measures "d38" distance of L0.end L5.end
extrude "Extrude7" add sketch "Sketch6" against normal up to surface (136.525 mm away) contours L0 A1 L6 | L0 A1 picked at (59.0752, 59.6844)
sketch "Sketch7" plane through (136.525, 0, 0) normal (1, 0, 0) x (0, 1, 0)
  line L0 (57.15, 63.5) -> (0, 63.5)
  line L1 (0, 63.5) -> (0, 66.675)
  line L2 (0, 66.675) -> (-3.0994, 66.675)
  arc A0 (-3.0994, 66.675) -> (24.356, 9.525) centre (63.5, 63.5) ccw
  line L3 (24.356, 9.525) -> (52.4278, 9.525)
  line L4 (52.4278, 9.525) -> (62.4918, 56.9043)
  arc A1 (62.4918, 56.9043) -> (57.15, 63.5) centre (57.15, 58.039) ccw
  line L5 (58.801, 59.69) -> (55.499, 59.69)
  line L6 (55.499, 59.69) -> (55.499, 56.388)
  line L7 (55.499, 56.388) -> (58.801, 56.388)
  line L8 (58.801, 56.388) -> (58.801, 59.69)
  line L9 (58.801, 59.69) -> (55.499, 56.388) construction
  line L10 (55.499, 59.69) -> (58.801, 56.388) construction
  point P0 (57.15, 58.039)
  dimension "d41" = 3.302
  dimension "d42" = 3.302
  constraint horizontal L5
  constraint perpendicular L5 L6
  constraint parallel L5 L7
  constraint parallel L6 L8
  constraint coincident L9 P0
  constraint coincident L10 P0
  constraint coincident P0 A1.centre
  measures "d41" distance of L6.end L7.end
  measures "d42" distance of L5.end L6.end
extrude "Extrude8" cut sketch "Sketch7" against normal blind 180.34 contours L5 L6 L7 L8

design "Left Cross Base Beam"
Autodesk Fusion 360 part; units mm, degrees
sketch "Sketch1" plane through (0, 0, 0) normal (1, 0, 0) x (0, 1, 0)
  circle A0 centre (0, 0) radius 2.1971
  circle A1 centre (25.4, 0) radius 2.1971
  line L0 (10.16, 2.54) -> (15.24, 2.54)
  line L1 (15.24, 2.54) -> (15.24, -2.54)
  line L2 (15.24, -2.54) -> (10.16, -2.54)
  line L3 (10.16, -2.54) -> (10.16, 2.54)
  line L4 (-6.35, 4.7625) -> (31.75, 4.7625)
  line L5 (31.75, 4.7625) -> (31.75, -4.7625)
  line L6 (31.75, -4.7625) -> (-6.35, -4.7625)
  line L7 (-6.35, -4.7625) -> (-6.35, 4.7625)
  dimension "d1" = 25.4
  dimension "d2" = 4.3942
  dimension "d3" = 4.3942
  dimension "d4" = 5.08
  dimension "d5" = 5.08
  dimension "d6" = 2.54
  dimension "d7" = 10.16
  dimension "d8" = 9.525
  dimension "d9" = 38.1
  dimension "d10" = 4.7625
  dimension "d11" = 6.35
  constraint horizontal A0.centre A1.centre
  constraint horizontal L0
  constraint vertical L1
  constraint horizontal L2
  constraint vertical L3
  constraint coincident A0.centre origin
  constraint horizontal L4
  constraint vertical L5
  constraint horizontal L6
  constraint vertical L7
  measures "d1" distance of A0.centre A1.centre
  measures "d2" diameter of A0
  measures "d3" diameter of A1
  measures "d4" distance of L0.start L0.end
  measures "d5" distance of L0.start L2.end
  measures "d6" distance of A0.centre L0
  measures "d7" horizontal distance of A0.centre L2.end
  measures "d8" distance of L4.start L6.end
  measures "d9" distance of L4.start L4.end
  measures "d10" distance of A0.centre L4
  measures "d11" distance of A0.centre L7
extrude "Extrude1" add sketch "Sketch1" along normal blind 2.54
sketch "Sketch2" plane through (2.54, 0, 0) normal (1, 0, 0) x (0, 1, 0)
  line L0 (15.24, -2.54) -> (10.16, -2.54)
  line L1 (10.16, -2.54) -> (10.16, 2.54)
  line L2 (10.16, 2.54) -> (15.24, 2.54)
  line L3 (15.24, 2.54) -> (15.24, -2.54)
  circle A0 centre (0, 0) radius 2.1971
  circle A1 centre (25.4, 0) radius 2.1971
  line L4 (-6.35, -4.7625) -> (31.75, -4.7625)
  line L5 (31.75, -4.7625) -> (31.75, 4.7625)
  line L6 (31.75, 4.7625) -> (-6.35, 4.7625)
  line L7 (-6.35, 4.7625) -> (-6.35, -4.7625)
  line L8 (31.75, 4.7625) -> (-6.35, 4.7625)
  line L9 (-6.35, 4.7625) -> (-6.35, -4.7625)
  line L10 (-6.35, -4.7625) -> (31.75, -4.7625)
  line L11 (31.75, -4.7625) -> (31.75, 4.7625)
  circle A2 centre (0, 0) radius 2.1971
  circle A3 centre (25.4, 0) radius 2.1971
  dimension "d14" = 4.3942
  dimension "d15" = 4.3942
  constraint horizontal L8
  constraint vertical L9
  constraint horizontal L10
  constraint vertical L11
  constraint coincident L4.start L7.end
  constraint coincident L5.end L6.start
  constraint concentric A0 A2
  constraint concentric A1 A3
  measures "d14" diameter of A2
  measures "d15" diameter of A3
extrude "Extrude2" add sketch "Sketch2" along normal blind 3.81 contours L0 L1 L2 L3 | L4 L5 L6 L7 L8 L9 L10 L11
sketch "Sketch3" plane through (0, -6.35, 0) normal (0, -1, 0) x (1, 0, 0)
  line L0 (0, 4.7625) -> (0, -4.7625)
  line L1 (0, -4.7625) -> (6.35, -4.7625)
  line L2 (6.35, -4.7625) -> (6.35, 4.7625)
  line L3 (6.35, 4.7625) -> (0, 4.7625)
  line L4 (0, 4.7625) -> (6.35, 4.7625)
  line L5 (6.35, 4.7625) -> (6.35, -4.7625)
  line L6 (6.35, -4.7625) -> (0, -4.7625)
  line L7 (0, -4.7625) -> (0, 4.7625)
  constraint horizontal L4
  constraint vertical L5
  constraint horizontal L6
  constraint vertical L7
  constraint coincident L1.end L2.start
  constraint coincident L0.start L3.end
extrude "Extrude3" add sketch "Sketch3" along normal blind 127
sketch "Sketch4" plane through (6.35, 0, 0) normal (1, 0, 0) x (0, 1, 0)
  circle A0 centre (0, 0) radius 2.1971
  circle A1 centre (25.4, 0) radius 2.1971
  line L0 (31.75, -4.7625) -> (31.75, 4.7625)
  line L1 (31.75, 4.7625) -> (-133.35, 4.7625)
  line L2 (-133.35, 4.7625) -> (-133.35, -4.7625)
  line L3 (-133.35, -4.7625) -> (31.75, -4.7625)
  circle A2 centre (-47.625, 1.5875) radius 1.6
  circle A3 centre (-22.225, 1.5875) radius 1.6
  dimension "d20" = 22.225
  dimension "d22" = 3.2
  dimension "d23" = 3.2
  dimension "d27" = 6.35
  dimension "d62" = 25.4
  constraint horizontal A2.centre A3.centre
  measures "d20" horizontal distance of A0.centre A3.centre
  measures "d22" diameter of A2
  measures "d23" diameter of A3
  measures "d27" distance of L3 A3.centre
  measures "d62" distance of A2.centre A3.centre
extrude "Extrude4" cut sketch "Sketch4" against normal blind 6.35 contours A2 | A3
sketch "Sketch6" plane through (0, -133.35, 0) normal (0, -1, 0) x (1, 0, 0)
  line L0 (0, -4.7625) -> (6.35, -4.7625)
  line L1 (6.35, -4.7625) -> (6.35, 4.7625)
  line L2 (6.35, 4.7625) -> (0, 4.7625)
  line L3 (0, 4.7625) -> (0, -4.7625)
  line L4 (0, 4.7625) -> (6.35, 4.7625)
  line L5 (6.35, 4.7625) -> (6.35, -1.5875)
  line L6 (6.35, -1.5875) -> (0, -1.5875)
  line L7 (0, -1.5875) -> (0, 4.7625)
  dimension "d29" = 6.35
  dimension "d30" = 6.35
  constraint horizontal L4
  constraint vertical L5
  constraint horizontal L6
  constraint vertical L7
  constraint coincident L2.end L3.start
  measures "d29" distance of L2.end L1.end
  measures "d30" distance of L2.end L6.end
extrude "Extrude5" cut sketch "Sketch6" against normal blind 67.945 contours L0 L1 L3 L6
sketch "Sketch7" plane through (0, 0, 0) normal (-1, 0, 0) x (0, -1, 0)
  line L0 (65.405, -4.7625) -> (65.405, -1.5875)
  line L1 (65.405, -1.5875) -> (133.35, -1.5875)
  line L2 (133.35, -1.5875) -> (133.35, 4.7625)
  line L3 (133.35, 4.7625) -> (-31.75, 4.7625)
  line L4 (-31.75, 4.7625) -> (-31.75, -4.7625)
  line L5 (-31.75, -4.7625) -> (65.405, -4.7625)
  line L6 (-10.16, -2.54) -> (-15.24, -2.54)
  line L7 (-15.24, -2.54) -> (-15.24, 2.54)
  line L8 (-15.24, 2.54) -> (-10.16, 2.54)
  line L9 (-10.16, 2.54) -> (-10.16, -2.54)
  circle A0 centre (-25.4, 0) radius 2.1971
  circle A1 centre (0, 0) radius 2.1971
  circle A2 centre (22.225, 1.5875) radius 1.6
  circle A3 centre (47.625, 1.5875) radius 1.6
  circle A4 centre (117.475, 1.5875) radius 2.1
  dimension "d33" = 4.2
  dimension "d34" = 3.175
  dimension "d35" = 15.875
  measures "d33" diameter of A4
  measures "d34" distance of L3 A4.centre
  measures "d35" distance of L2 A4.centre
extrude "Extrude6" cut sketch "Sketch7" against normal blind 6.35 contours A4
sketch "Sketch8" plane through (0, 0, 0) normal (-1, 0, 0) x (0, -1, 0)
  circle A0 centre (117.475, 1.5875) radius 2.1
  line L0 (65.405, -4.7625) -> (65.405, -1.5875)
  line L1 (65.405, -1.5875) -> (133.35, -1.5875)
  line L2 (133.35, -1.5875) -> (133.35, 4.7625)
  line L3 (133.35, 4.7625) -> (-31.75, 4.7625)
  line L4 (-31.75, 4.7625) -> (-31.75, -4.7625)
  line L5 (-31.75, -4.7625) -> (65.405, -4.7625)
  line L6 (-10.16, -2.54) -> (-15.24, -2.54)
  line L7 (-15.24, -2.54) -> (-15.24, 2.54)
  line L8 (-15.24, 2.54) -> (-10.16, 2.54)
  line L9 (-10.16, 2.54) -> (-10.16, -2.54)
  circle A1 centre (-25.4, 0) radius 2.1971
  circle A2 centre (0, 0) radius 2.1971
  circle A3 centre (22.225, 1.5875) radius 1.6
  circle A4 centre (47.625, 1.5875) radius 1.6
  circle A5 centre (117.475, 11.4427) radius 2.1
  circle A6 centre (117.475, 11.4427) radius 3.175
  circle A7 centre (106.045, 11.4427) radius 2.1
  circle A8 centre (106.045, 11.4427) radius 3.175
  line L10 (117.475, 8.2677) -> (106.045, 8.2677)
  line L11 (117.475, 14.6177) -> (106.045, 14.6177)
  line L12 (106.045, 14.6177) -> (70.9402, 14.6177)
  line L13 (70.9402, 14.6177) -> (65.405, 6.5046)
  line L14 (106.045, 8.2677) -> (74.295, 8.2677)
  line L15 (74.295, 8.2677) -> (65.405, -4.7625)
  line L16 (65.405, 6.5046) -> (65.405, -4.7625)
  line L17 (65.405, 6.5046) -> (64.2164, 4.7625)
  dimension "d38" = 4.2
  dimension "d39" = 9.8552
  dimension "d40" = 6.35
  dimension "d45" = 4.2
  dimension "d46" = 6.35
  dimension "d47" = 11.43
  dimension "d66" = 6.35
  dimension "d68" = 31.75
  dimension "d69" = 6.35
  constraint vertical A0.centre A5.centre
  constraint concentric A5 A6
  constraint concentric A7 A8
  constraint horizontal A5.centre A7.centre
  constraint coincident A6 L10.start
  constraint coincident A8 L10.end
  constraint coincident A6 L11.start
  constraint coincident A8 L11.end
  constraint tangent A8 L11
  constraint horizontal L10
  constraint horizontal L11
  constraint parallel L11 L12
  constraint parallel L3 L14
  constraint coincident L0.start L5.end
  constraint parallel L13 L15
  constraint vertical L13.end L0.start
  constraint coincident L3 L17.end
  constraint parallel L13 L17
  measures "d38" diameter of A5
  measures "d39" vertical distance of A0.centre A5.centre
  measures "d40" diameter of A6
  measures "d45" diameter of A7
  measures "d46" diameter of A8
  measures "d47" distance of A5.centre A7.centre
  measures "d66" distance of L12 L14
  measures "d68" distance of L10.end L14.end
  measures "d69" distance of L13 L15
extrude "Extrude7" cut sketch "Sketch8" against normal blind 6.35 contours L0 L1 L15 L16 | L1 L2 L3 L15 | A1 | A2 | A3 | A4